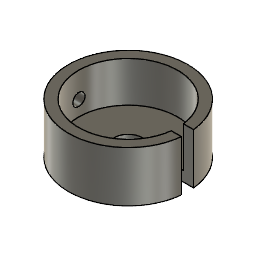
Probe Tube Cap (Autodesk Fusion 360 design; units mm, degrees)
Autodesk Fusion 360 part; units mm, degrees
sketch "Sketch1" plane through (0, 0, 0) normal (0, 0, 1) x (1, 0, 0)
  circle A0 centre (0, 0) radius 24.5
  circle A1 centre (0, 0) radius 29.5
  dimension "d1" = 49
  dimension "d2" = 5
  constraint coincident A0.centre A1.centre
  measures "d1" diameter of A0
extrude "Extrude1" add sketch "Sketch1" along normal blind 5 contours A0 | A1
extrude "Extrude2" add sketch "Sketch1" along normal blind 25
sketch "Sketch2" plane through (0, 0, 0) normal (0, 0, -1) x (1, 0, 0)
  circle A0 centre (0, 0) radius 29.5
  circle A1 centre (0, 0) radius 6.875
  line L0 (6.875, -3) -> (33.2051, -3)
  arc A2 (33.2051, -3) -> (33.2051, 3) centre (33.2051, 0) ccw
  line L1 (33.2051, 3) -> (6.875, 3)
  arc A3 (6.875, 3) -> (6.875, -3) centre (6.875, 0) ccw
  line L2 (6.875, 0) -> (33.2051, 0) construction
  dimension "d7" = 13.75
  dimension "d8" = 6
  constraint coincident A0.centre A1.centre
  constraint tangent L0 A2
  constraint tangent A2 L1
  constraint parallel L0 L1
  constraint tangent L1 A3
  constraint tangent L0 A3
  constraint horizontal L2
  constraint coincident A1 A3.centre
  measures "d7" diameter of A1
  measures "d8" diameter of A2
extrude "Extrude3" cut sketch "Sketch2" against normal blind 45 contours A0 A1 L0 L1 A3 | A1 A3 | A1 A3 picked at (14.3411, -2.3348)
ref_plane "WorkPlane1" through (-29.5, 0, 19.6682) normal (-1, 0, 0) x (0, 1, 0)
sketch "Sketch3" plane through (-29.5, 0, 0) normal (-1, 0, 0) x (0, -1, 0)
  line L0 (0, 25) -> (0, 0) construction
  circle A0 centre (0, 12.5) radius 3
  dimension "d12" = 6
  constraint coincident L0.end origin
  constraint vertical L0
  constraint midpoint L0 A0.centre
  measures "d12" diameter of A0
extrude "Extrude4" cut sketch "Sketch3" against normal blind 14
